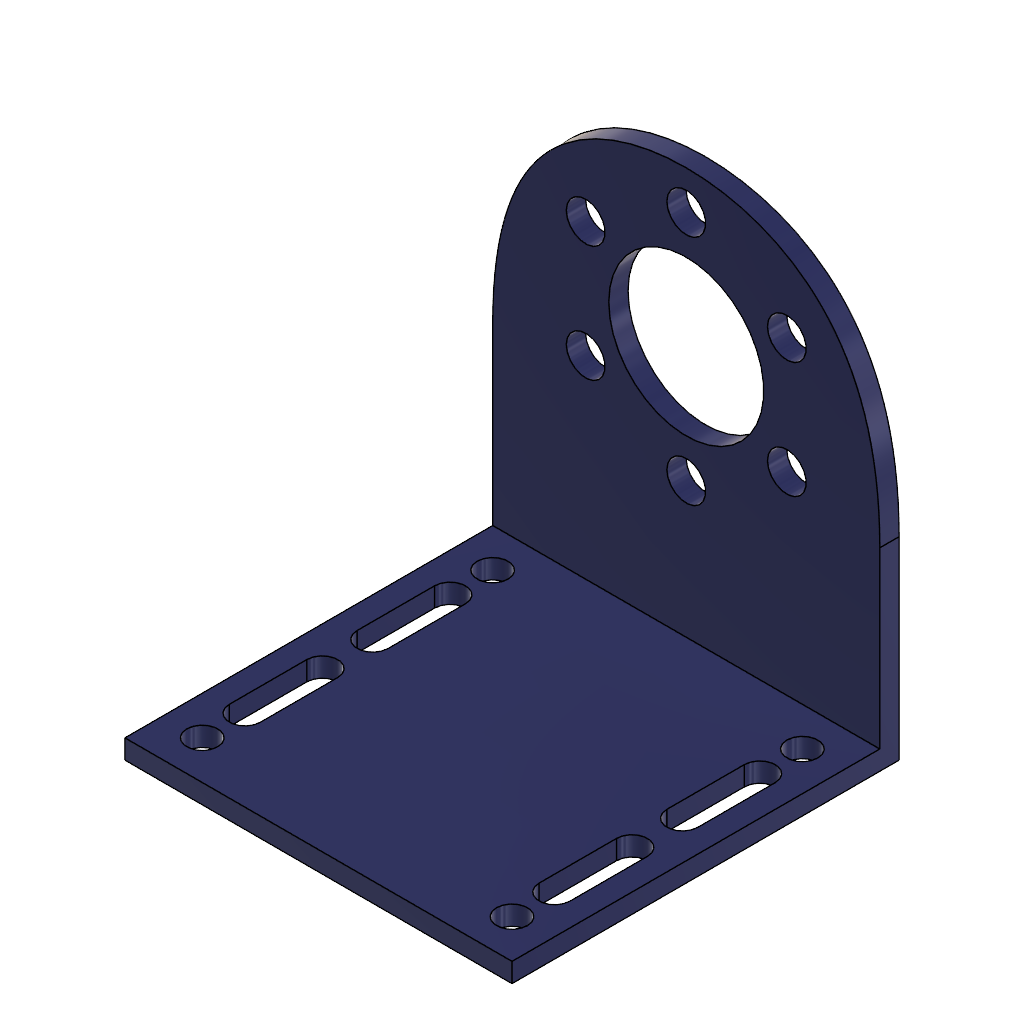
support_moteur (Autodesk Fusion 360 design; units mm, degrees)
part number: 2026-10-28-08-01-39-424
Autodesk Fusion 360 part; units mm, degrees
sketch "Esquisse1" plane through (0, 0, 0) normal (0, 1, 0) x (1, 0, 0)
  line L0 (-50, 0) -> (50, 0)
  line L1 (50, 0) -> (50, -50)
  line L2 (-50, 0) -> (-50, -50)
  line L3 (-20, -110) -> (53.0512, -110) construction
  spline S0 degree 5 poles (-50, -50) (-50, -55.2625) (-49.4895, -65.1399) (-47.1923, -78.013) (-41.2225, -91.4309) (-29.8028, -102.6337) (-15.612, -108.9826) (0, -111.0248) (15.612, -108.9826) (29.8028, -102.6337) (41.2225, -91.4309) (47.1923, -78.013) (49.4895, -65.1399) (50, -55.2625) (50, -50) knots 0 0 0 0 0 0 0.1 0.2 0.3 0.4 0.5 0.6 0.7 0.8 0.9 1 1 1 1 1 1
  line L4 (-80, -70) -> (86.7138, -70) construction
  circle A0 centre (0, -70) radius 20
  line L5 (-70, -100) -> (84.0249, -100) construction
  circle A1 centre (0, -100) radius 5
  circle A2 centre (25.9808, -85) radius 5
  circle A3 centre (25.9808, -55) radius 5
  circle A4 centre (0, -40) radius 5
  circle A5 centre (-25.9808, -55) radius 5
  circle A6 centre (-25.9808, -85) radius 5
  line L6 (-50, -5) -> (50, -5)
  point P0 (0, -110)
  dimension "d1" = 100
  dimension "d2" = 50
  dimension "d3" = 50
  dimension "d4" = 40
  dimension "d6" = 40
  dimension "d7" = 30
  dimension "d8" = 10
  dimension "d10" = 360
  dimension "d11" = 5
  constraint horizontal L0
  constraint perpendicular L0 L1
  constraint perpendicular L0 L2
  constraint horizontal L3
  constraint coincident L3 P0
  constraint horizontal L4
  constraint coincident L4 A0.centre
  constraint parallel L4 L5
  constraint coincident L5 A1.centre
  constraint coincident L2 L6.start
  constraint coincident L1 L6.end
  constraint perpendicular L1 L6
  measures "d1" distance of L0.start L0.end
  measures "d2" distance of origin L2
  measures "d3" distance of L0.end L1.end
  measures "d4" distance of P0 L4
  measures "d6" diameter of A0
  measures "d7" distance of L4 L5
  measures "d8" diameter of A1
  measures "d11" distance of L0 L6
extrude "Extrusion2" add sketch "Esquisse1" against normal blind 5
extrude "Extrusion3" add sketch "Esquisse1" against normal blind 100 contours L0 L1 L2 L6
sketch "Esquisse2" plane through (0, 0, 5) normal (0, 0, 1) x (-1, 0, 0)
  line L0 (-50, 5) -> (50, 5)
  line L1 (50, 5) -> (50, 100)
  line L2 (50, 100) -> (-50, 100)
  line L3 (-50, 100) -> (-50, 5)
  line L4 (40, -20) -> (40, 115.4648) construction
  line L5 (100, 15) -> (-70, 15) construction
  circle A0 centre (40, 15) radius 4
  line L6 (100.0812, 26) -> (-70, 26) construction
  line L7 (44, 26) -> (44, 46)
  arc A1 (44, 46) -> (36, 46) centre (40, 46) ccw
  line L8 (36, 46) -> (36, 26)
  arc A2 (36, 26) -> (44, 26) centre (40, 26) ccw
  line L9 (40, 26) -> (40, 46) construction
  circle A3 centre (-40, 15) radius 4
  line L10 (-36, 26) -> (-36, 46)
  arc A4 (-36, 46) -> (-44, 46) centre (-40, 46) ccw
  arc A5 (-44, 26) -> (-36, 26) centre (-40, 26) ccw
  line L11 (-44, 46) -> (-44, 26)
  line L12 (110, 52.5) -> (-113.2229, 52.5) construction
  circle A6 centre (40, 90) radius 4
  line L13 (44, 79) -> (44, 59)
  arc A7 (36, 59) -> (44, 59) centre (40, 59) ccw
  arc A8 (44, 79) -> (36, 79) centre (40, 79) ccw
  line L14 (36, 59) -> (36, 79)
  circle A9 centre (-40, 90) radius 4
  line L15 (-36, 79) -> (-36, 59)
  arc A10 (-44, 59) -> (-36, 59) centre (-40, 59) ccw
  arc A11 (-36, 79) -> (-44, 79) centre (-40, 79) ccw
  line L16 (-44, 59) -> (-44, 79)
  dimension "d18" = 10
  dimension "d19" = 10
  dimension "d20" = 8
  dimension "d21" = 11
  dimension "d22" = 8
  dimension "d25" = -80
  dimension "d26" = 0
  dimension "d27" = 47.5
  constraint perpendicular L2 L4
  constraint horizontal L5
  constraint coincident L4 A0.centre
  constraint coincident L5 A0.centre
  constraint perpendicular L4 L6
  constraint tangent L7 A1
  constraint tangent A1 L8
  constraint parallel L7 L8
  constraint tangent L8 A2
  constraint tangent L7 A2
  constraint perpendicular L6 L9
  constraint coincident L4 A2.centre
  constraint coincident L6 A2.centre
  constraint horizontal L12
  constraint symmetric A0 L12 A6
  constraint symmetric L7.start L12 L13.start
  constraint symmetric L7.end L12 L13.end
  constraint symmetric A1.end L12 A7.start
  constraint symmetric L8.end L12 A8.end
  constraint symmetric A1 L12 A7
  constraint symmetric A2 L12 A8
  constraint symmetric A3 L12 A9
  constraint symmetric L10.start L12 L15.start
  constraint symmetric L10.end L12 L15.end
  constraint symmetric A4.end L12 A10.start
  constraint symmetric A4 L12 A10
  constraint symmetric A5.start L12 A11.end
  constraint symmetric A5 L12 A11
  measures "d18" distance of L1 L4
  measures "d19" distance of L0 L5
  measures "d20" diameter of A0
  measures "d21" distance of L5 L6
  measures "d22" diameter of A1
  measures "d27" distance of L0 L12
extrude "Extrusion4" cut sketch "Esquisse2" against normal blind 20 contours A0 | L7 A1 L8 A2 | A3 | L10 A4 A5 L11 | A6 | L13 A7 A8 L14 | A9 | L15 A10 A11 L16
equation "d27 = ( 95 / 2 ) * 1 mm"
